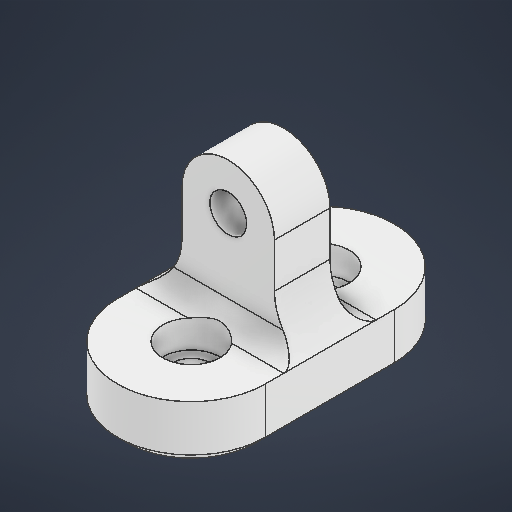
# Autodesk Inventor part: Link Support Parts
Saved by Autodesk Inventor 2026.2 (Build 302298010, 298A)
## iProperties
Created: 2026-05-08
Part Number: Link Support Parts
Material: ABS 플라스틱
Document SubType Name: Modeling
Designer: work
Density: 1.06 g/cm^3
Appearance: 매끄러움 - 흰색
Author: work
Autodesk Inventor part; units mm, degrees
ref_plane "YZ Plane" through (0, 0, 0) normal (1, 0, 0) x (0, 1, 0)
ref_plane "XZ Plane" through (0, 0, 0) normal (0, 1, 0) x (-1, 0, 0)
ref_plane "XY Plane" through (0, 0, 0) normal (0, 0, 1) x (1, 0, 0)
sketch "스케치1" plane through (0, 0, 0) normal (0, 1, 0) x (-1, 0, 0)
  line L0 (0, 7) -> (0, -7) construction
  circle A0 centre (0, 7) radius 2
  circle A1 centre (0, -7) radius 2
  line L1 (0, 7) -> (0, -7) construction
  line L2 (-8, 7) -> (-8, -7)
  line L3 (8, -7) -> (8, 7)
  arc A2 (8, 7) -> (-8, 7) centre (0, 7) ccw
  arc A3 (-8, -7) -> (8, -7) centre (0, -7) ccw
  point P0 (0, 0)
  point P1 (0, 0)
  dimension "d0" = 14
  dimension "d1" = 4
  dimension "d2" = 4
  dimension "d3" = 8
  constraints: 10 end point, 4 centre point, 4 point on circle, 4 tangent, 2 coincident, 2 equal length, 2 midpoint, 1 vertical
  measures "d0" distance of L0.start L0.end
  measures "d1" diameter of A0
  measures "d2" diameter of A1
  measures "d3" radius of A3
extrude "돌출1" add sketch "스케치1" along normal blind 6
sketch "스케치2" plane through (0, 6, 0) normal (0, 1, 0) x (1, 0, 0)
  circle A0 centre (0, -7) radius 2 projected
  circle A1 centre (0, 7) radius 2 projected
  point P0 (0, 0)
  constraints: 2 coincident
hole "구멍1" at (0, 6, 7) at (0, 6, -7) direction (0, -1, 0) diameter 4 end through all counterbore diameter 6.2 counterbore depth 3
sketch "스케치3" plane through (0, 0, 0) normal (0, 0, 1) x (1, 0, 0)
  line L0 (8, 6) -> (-8, 6) projected
  line L1 (0, 6) -> (0, 16) construction
  line L2 (5, 6) -> (5, 16)
  line L3 (-5, 16) -> (-5, 6)
  arc A0 (-5, 6) -> (5, 6) centre (0, 6) ccw
  arc A1 (5, 16) -> (-5, 16) centre (0, 16) ccw
  circle A2 centre (0, 16) radius 2
  point P0 (0, 0)
  point P1 (0, 11)
  dimension "d13" = 4
  dimension "d14" = 10
  dimension "d15" = 5
  constraints: 8 end point, 4 point on circle, 4 tangent, 3 centre point, 2 midpoint, 1 coincident, 1 parallel, 1 perpendicular
  measures "d13" diameter of A2
  measures "d14" distance of L1.start L1.end
  measures "d15" radius of A1
extrude "돌출2" add sketch "스케치3" along normal mid plane 6 contours L0 L3 A1 L2
fillet "모깎기1" radius 6 2 edges at (-5, 6, 0) (5, 6, 0)
fillet "모깎기2" radius 2 2 edges at (0, 6, 3) (0, 6, -3)
chamfer "모따기1" distance 1 angle 45 4 edges at (8, 0, 0) (0, 0, -15) (-8, 0, 0) (0, 0, 15)
